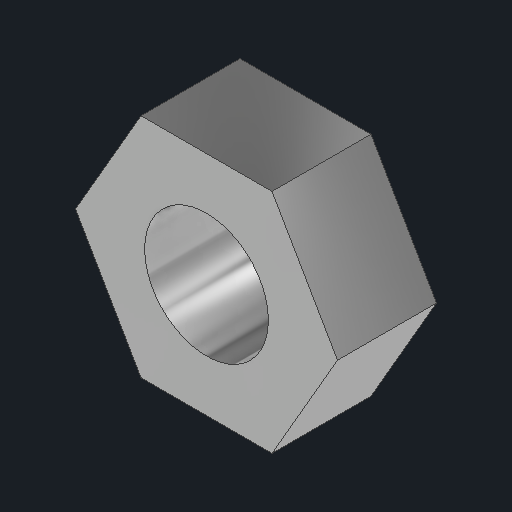
# Autodesk Inventor part: nut_M3
Saved by Autodesk Inventor 2027.1 (Build 311270010, 270A)
## iProperties
Created: 2026-11-09
Part Number: nut_M3
Material: Generic
Description: Hex nut M3 ISO 4032 (5.5 AF, 2.4 thick)
Document SubType Name: Modeling
Designer: alexg
Density: 1 g/cm^3
Appearance: Stainless Steel - Bright
Author: alexg
Autodesk Inventor part; units mm, degrees
ref_plane "YZ Plane" through (0, 0, 0) normal (1, 0, 0) x (0, 1, 0)
ref_plane "XZ Plane" through (0, 0, 0) normal (0, 1, 0) x (-1, 0, 0)
ref_plane "XY Plane" through (0, 0, 0) normal (0, 0, 1) x (1, 0, 0)
sketch "Hex sketch" plane through (0, 0, 0) normal (0, 0, 1) x (1, 0, 0)
  line L0 (3.1754, 0) -> (1.5877, 2.75)
  line L1 (1.5877, 2.75) -> (-1.5877, 2.75)
  line L2 (-1.5877, 2.75) -> (-3.1754, 0)
  line L3 (-3.1754, 0) -> (-1.5877, -2.75)
  line L4 (-1.5877, -2.75) -> (1.5877, -2.75)
  line L5 (1.5877, -2.75) -> (3.1754, 0)
  constraints: 12 end point
extrude "Hex" add sketch "Hex sketch" along normal blind 2.4
sketch "Thread bore sketch" plane through (0, 0, 0) normal (0, 0, 1) x (1, 0, 0)
  circle A0 centre (0, 0) radius 1.5
  constraints: 1 centre point
extrude "Thread bore" cut sketch "Thread bore sketch" along normal blind 2.4
body "Solid1"
